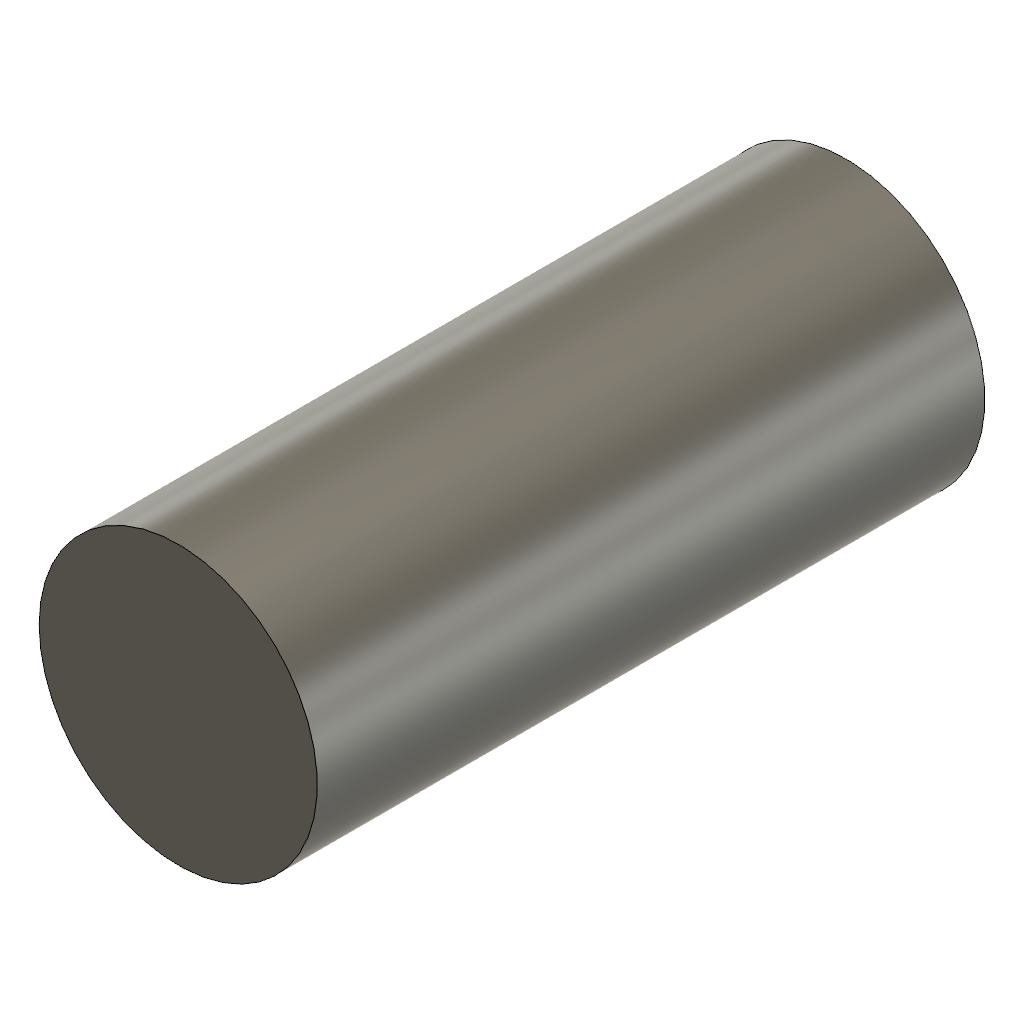
symmetric_half (Autodesk Fusion 360 design; units mm, degrees)
part number: 2026-10-20-17-27-18-483
Autodesk Fusion 360 part; units mm, degrees
sketch "ProbeProfile" plane through (0, 0, 0) normal (0, 0, 1) x (1, 0, 0)
  circle A0 centre (0, 0) radius 10
extrude "ProbeExtrusion" add sketch "ProbeProfile" along normal mid plane 48
